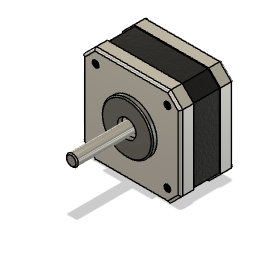
NEMA17 stepper motor v39 (Autodesk Fusion 360 design; units mm, degrees)
Autodesk Fusion 360 part; units mm, degrees
sketch "Skizze1" plane through (0, 0, 0) normal (0, 0, 1) x (1, 0, 0)
  line L0 (-21.15, 21.15) -> (21.15, 21.15)
  line L1 (21.15, 21.15) -> (21.15, -21.15)
  line L2 (21.15, -21.15) -> (-21.15, -21.15)
  line L3 (-21.15, -21.15) -> (-21.15, 21.15)
  line L4 (21.15, 0) -> (-21.15, 0) construction
  line L5 (0, 21.15) -> (0, -21.15) construction
  line L6 (-15.5, 15.5) -> (15.5, 15.5) construction
  line L7 (15.5, 15.5) -> (15.5, -15.5) construction
  line L8 (15.5, -15.5) -> (-15.5, -15.5) construction
  line L9 (-15.5, -15.5) -> (-15.5, 15.5) construction
  line L10 (0, 15.5) -> (0, -15.5) construction
  line L11 (-15.5, 0) -> (15.5, 0) construction
  circle A0 centre (0, 0) radius 11
  circle A1 centre (0, 0) radius 2.5
  circle A2 centre (0, 0) radius 4
  point P0 (15.5, 15.5)
  point P1 (15.5, -15.5)
  point P2 (-15.5, -15.5)
  point P3 (-15.5, 15.5)
  dimension "d1" = 42.3
  dimension "d2" = 42.3
  dimension "d3" = 31
  dimension "d4" = 31
  dimension "d5" = 22
  dimension "d9" = 5
  dimension "d22" = 8
  constraint horizontal L0
  constraint vertical L1
  constraint horizontal L2
  constraint vertical L3
  constraint midpoint L1 L4.start
  constraint midpoint L3 L4.end
  constraint midpoint L0 L5.start
  constraint midpoint L2 L5.end
  constraint midpoint L4 A0.centre
  constraint coincident A0.centre A1.centre
  constraint horizontal L6
  constraint vertical L7
  constraint horizontal L8
  constraint vertical L9
  constraint midpoint L6 L10.start
  constraint midpoint L8 L10.end
  constraint midpoint L9 L11.start
  constraint midpoint L7 L11.end
  constraint midpoint L11 A0.centre
  constraint coincident P0 L6.end
  constraint coincident P1 L7.end
  constraint coincident P2 L8.end
  constraint coincident P3 L6.start
  measures "d1" distance of L0.start L0.end
  measures "d2" distance of L0.start L2.end
  measures "d3" distance of P3 P0
  measures "d4" distance of P3 P2
  measures "d5" diameter of A0
  measures "d9" diameter of A1
  measures "d22" diameter of A2
extrude "Extrusion1" add sketch "Skizze1" along normal blind 2 contours A0 | A1 | A2 makes body 1
extrude "Extrusion2" add sketch "Skizze1" against normal blind 5.75 separate body contours L0 L1 L2 L3 | A0 | A2 makes body 2
hole "Bohrung1" at (15.5, 15.5, 0) at (-15.5, 15.5, 0) at (-15.5, -15.5, 0) at (15.5, -15.5, 0) direction (0, 0, -1) diameter 2.529 depth 4.5 tip angle 118 countersink diameter 2.782 countersink angle 90 bodies 2
thread "Gewinde1" "ISO Metric profile 3.0 M3x0.5 6H" major diameter 3.086 minor diameter 2.529 pitch 0.5 angle 60 modelled right hand crest width 0.1368 on face at (15.6259, 14.2418, -1.5843) crest through (16.7645, 15.5, -0.2515) on face at (-15.3741, 14.2418, -1.5843) crest through (-14.2355, 15.5, -0.2515) on face at (-15.3741, -16.7582, -1.5843) crest through (-14.2355, -15.5, -0.2515) on face at (15.6259, -16.7582, -1.5843) crest through (16.7645, -15.5, -0.2515) on bodies 2
extrude "Extrusion3" add sketch "Skizze1" along normal blind 26 and the other way blind 23 separate body contours A1 makes body 3
chamfer "Fase2" distance 0.5 angle 45 2 edges at (-2.3308, 0.904, -23) (-2.3308, -0.904, 26) on bodies 3
extrude "Extrusion4" cut sketch "Skizze1" along normal blind 2 contours A1 | A2 bodies 1
extrude "Extrusion5" add 1 faces at (0.0623, 14.931, -5.75) along direction (0, 0, -1) blind 11.5 separate body on bodies 2 makes body 4
extrude "Extrusion6" add 1 faces at (0.0623, 14.931, -17.25) along direction (0, 0, -1) blind 5.75 separate body on bodies 4 makes body 5
sketch "Skizze2" plane through (0, 0, -23) normal (0, 0, -1) x (-1, 0, 0)
  circle A0 centre (0, 0) radius 2.5
  line L0 (-21.15, -21.15) -> (21.15, -21.15)
  line L1 (21.15, -21.15) -> (21.15, 21.15)
  line L2 (21.15, 21.15) -> (-21.15, 21.15)
  line L3 (-21.15, 21.15) -> (-21.15, -21.15)
  circle A1 centre (0, 0) radius 4
extrude "Extrusion7" cut sketch "Skizze2" against normal blind 2 contours A1 bodies 5
chamfer "Fase1" distance 5 angle 45 12 edges at (-21.15, 21.15, -11.5) (21.15, 21.15, -11.5) (21.15, -21.15, -11.5) (-21.15, -21.15, -11.5) (-21.15, 21.15, -20.125) (21.15, 21.15, -20.125) (21.15, -21.15, -20.125) (-21.15, -21.15, -20.125) (-21.15, 21.15, -2.875) (21.15, 21.15, -2.875) (21.15, -21.15, -2.875) (-21.15, -21.15, -2.875) on bodies 2 4 5
fillet "Abrundung1" radius 1 8 edges at (0, 21.15, 0) (18.65, 18.65, 0) (21.15, 0, 0) (18.65, -18.65, 0) (0, -21.15, 0) (-18.65, -18.65, 0) (-21.15, 0, 0) (-18.65, 18.65, 0) on bodies 2 5
fillet "Abrundung1" radius 1 8 edges at (0, 21.15, -23) (18.65, 18.65, -23) (21.15, 0, -23) (-21.15, 0, -23) (-18.65, 18.65, -23) (-18.65, -18.65, -23) (0, -21.15, -23) (18.65, -18.65, -23) on bodies 2 5
fillet "Abrundung2" radius 0.5 1 edges at (-10.2556, -3.9778, 2) on bodies 1
fillet "Abrundung3" radius 0.5 1 edges at (3.7293, 1.4465, -23) on bodies 5
scale "Maßstab1" factors (0.98, 0.98, 1) about (0, 0, 0) bodies 4
equation "d1 = Width"
equation "d2 = Width"
equation "d3 = FrontHoleDistance"
equation "d4 = FrontHoleDistance"
equation "d6 = BearingHubSize"
equation "ShaftSize = 5 mm"
equation "d9 = ShaftSize"
equation "Length = 23 mm"
equation "d11 = -CapLength"
equation "d18 = BearingHubSize + 24 mm"
equation "d20 = Length"
equation "CapLength = Length / 4"
equation "d26 = Length - 2 * CapLength"
equation "d28 = CapLength"
equation "BearingHubSize = 2 mm"
equation "FrontHoleDistance = 31 mm" comment "NEMA17: Fixed 31mm"
equation "Width = 42.3 mm" comment "NEMA17 42.0, but we use the max of 42.3mm"
named bodies: "Top cap", "Shaft", "Middle part", "End cap"
